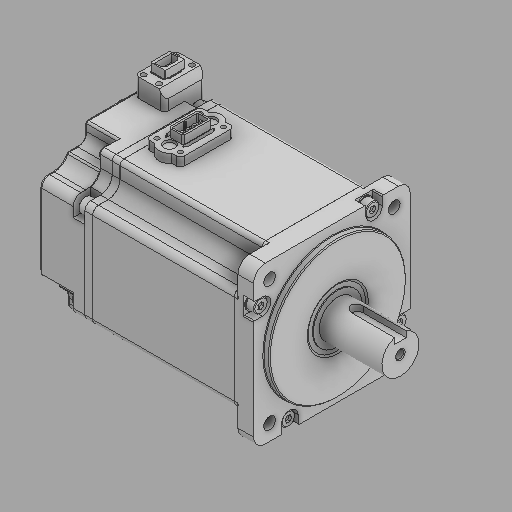
# Autodesk Inventor part: MSME082G1U_msmf_gh
Saved by Autodesk Inventor 2025.3 (Build 293356000, 356)
## iProperties
Category: PARTsolutions
Company: MATSUSHITA
Created: 2026-08-05
Part Number: MSME082G1U_msmf_gh
Material: Generisch
Catalog Web Link: www.3dfindit.com
Description: MSMF-gh-
Vendor: MATSUSHITA
Document SubType Name: Modeling
Designer: psAdmin
Manufacturer: MATSUSHITA
Mass: 644.906 g
Surface Area: 626.219 cm^2
Volume: 644.906 cm^3
Density: 1 g/cm^3
Appearance: PSOLRGB-176-176-176
PSOL_IDENT_0: {$CADENAS_DATA/23d-libs/matsushita/ac_servo_motor/servo_motor_wtout_gear/parts/a6_msmf_gear_head.prj
PSOL_IDENT_1: },185 {VTYP=3D},{NB=MSME082G1U_msmf_gh},{LINA=MSME082G1U},{NN=MSMF-gh},{DATE=04.12.2025 07:26:10},{G
PSOL_IDENT_2: EOMDATE=13.11.2025 11:41:00},{VERSION=},{LINEID=80},{WBVAR=E,B,EOS,OS,MS,PS},{WBNUMERIC=}  {NB=MSME0
PSOL_IDENT_3: 82G1U_msmf_gh},{LINA=MSME082G1U},{KT=DUMMY},{R=0.75 k},{E=G},{B=No},{EOS=With key and end of tap},{O
PSOL_IDENT_4: S=Yes},{MS=2},{PS=200},{CNSORDERNO=MSME082G1U},{X=U},{XR=08},{LM=114.5},{S=19},{X1=6},{KB1=56.5},{LR=
PSOL_IDENT_5: 55},{LK=42},{LH=45},{R1= '1.0 k','1.5 k','2.0 k','3.0 k','4.0 k','5.0 k' },{PS1=2},{PS2='200','400'}
PSOL_IDENT_6: ,{EOSX='Straight','Straight','D cut','D cut','With key and end of tap','With key and end of tap'},{O
PSOL_IDENT_7: SX='Yes','Yes','No','No'},{Z=5},{LX=147.2},{LLX=112.2},{LMX=86.2},{LTX=26},{LNX=0},{KB1X=52.4},{KB2X=
PSOL_IDENT_8: 85.7},{KB3X=0},{MS1= '2','IP67 motor' },{MS2=1},{XS=1},{BR=0},{XX=1}
NB: MSME082G1U_msmf_gh
NN: MSMF-gh
NBSYN: $CNSORDERNO._msmf_gh
LINA: MSME082G1U
CATALOG: Panasonic Industry Co., Ltd. , Motors for FA & Industrial Application
R: 0.75 k
E: 20bit Incremental
B: No
EOS: With key and end of tap
OS: Yes
MS: IP67 motor
PS: 200
CNSORDERNO: MSME082G1U
X1: 6
SUPPLIER: MATSUSHITA
ARTICLENO: MSME082G1U_msmf_gh
BOMINFO: MSME082G1U
CREATOR: CADENAS GmbH
Title: MSME082G1U
Author: Cadenas PARTsolutions
Autodesk Inventor part; units mm, degrees
ref_plane "YZ Plane" through (0, 0, 0) normal (1, 0, 0) x (0, 1, 0)
ref_plane "XZ Plane" through (0, 0, 0) normal (0, 1, 0) x (-1, 0, 0)
ref_plane "XY Plane" through (0, 0, 0) normal (0, 0, 1) x (1, 0, 0)
sketch "Sketch_3" plane through (0, 0, 0) normal (0, 0, 1) x (1, 0, 0)
  line L0 (0, 0) -> (-3, 0)
  line L1 (-3.5, 0) -> (-3.5, 35.5)
  line L2 (-3.5, 35.5) -> (-3, 35.5)
  line L3 (-3, 35.5) -> (-3, 35.3)
  arc A0 (-3, 35.3) -> (-2.7, 35) centre (-2.7, 35.3) ccw
  line L4 (-2.7, 35) -> (-0.5, 35)
  line L5 (-0.5, 35) -> (0, 34.5)
  line L6 (0, 34.5) -> (0, 15.566)
  line L7 (0, 15.566) -> (-0.5, 14.7)
  line L8 (-0.5, 14.7) -> (-0.5, 12.5)
  line L9 (-0.5, 12.5) -> (0, 12.5)
  line L10 (0, 12.5) -> (0, 0)
  line L11 (0, 0) -> (-3.5, 0)
  constraints: 24 end point, 2 point on circle, 1 centre point
revolve "Revolution1" add sketch "Sketch_3" angle 360 about axis through (0, 0, 0) along (1, 0, 0)
sketch "Sketch_2" plane through (0, 0, 0) normal (0, 0, 1) x (1, 0, 0)
  line L0 (32, 0) -> (0, 0)
  line L1 (0, 0) -> (0, 9.5)
  line L2 (0, 9.5) -> (32, 9.5)
  line L3 (32, 9.5) -> (32, 0)
  line L4 (32, 0) -> (0, 0)
  constraints: 10 end point
revolve "Revolution2" add sketch "Sketch_2" angle 360 about axis through (32, 0, 0) along (1, 0, 0)
sketch "Sketch_4" plane through (0, 6, 0) normal (0, 1, 0) x (1, 0, 0)
  arc A0 (10, 3) -> (10, -3) centre (10, 0) ccw
  line L0 (10, -3) -> (32, -3)
  line L1 (32, -3) -> (32, 3)
  line L2 (32, 3) -> (10, 3)
  constraints: 6 end point, 2 point on circle, 1 centre point
extrude "Extrusion1" cut sketch "Sketch_4" along normal blind 10
sketch "Sketch4" plane through (32, 6, 3) normal (1, 0, 0) x (0, 0, -1)
  point P0 (3, -6)
hole "Hole1" at (32, 0, 0) direction (-1, 0, 0) diameter 4.134 depth 11.8066 tip angle 120 countersink diameter 5 countersink angle 90 thread size "M5x0.8" class "6H" standard "ISO Metric profile"
sketch "Sketch_9" plane through (-3, 0, 0) normal (1, 0, 0) x (0, 0, -1)
  arc A0 (-40, -34) -> (-34, -40) centre (-34, -34) ccw
  line L0 (-34, -40) -> (34, -40)
  arc A1 (34, -40) -> (40, -34) centre (34, -34) ccw
  line L1 (40, -34) -> (40, 34)
  arc A2 (40, 34) -> (34, 40) centre (34, 34) ccw
  line L2 (34, 40) -> (-34, 40)
  arc A3 (-34, 40) -> (-40, 34) centre (-34, 34) ccw
  line L3 (-40, 34) -> (-40, -34)
  circle A4 centre (31.8198, 31.8198) radius 3
  circle A5 centre (31.8198, -31.8198) radius 3
  circle A6 centre (-31.8198, 31.8198) radius 3
  circle A7 centre (-31.8198, -31.8198) radius 3
  constraints: 8 centre point, 8 end point, 8 point on circle
extrude "Extrusion2" add sketch "Sketch_9" against normal blind 8
sketch "Sketch_10" plane through (-3, 0, 0) normal (1, 0, 0) x (0, 0, -1)
  line L0 (-40.5, 26.75) -> (-40.5, 16.25)
  line L1 (-40.5, 16.25) -> (-40, 16.25)
  line L2 (-40, 16.25) -> (-40, 16.75)
  arc A0 (-39.5, 17.25) -> (-40, 16.75) centre (-39.5, 16.75) ccw
  line L3 (-39.5, 17.25) -> (-35.5, 17.25)
  arc A1 (-35.5, 17.25) -> (-35.5, 25.75) centre (-35.5, 21.5) ccw
  line L4 (-35.5, 25.75) -> (-39.5, 25.75)
  arc A2 (-40, 26.25) -> (-39.5, 25.75) centre (-39.5, 26.25) ccw
  line L5 (-40, 26.25) -> (-40, 26.75)
  line L6 (-40, 26.75) -> (-40.5, 26.75)
  constraints: 14 end point, 6 point on circle, 3 centre point
extrude "Extrusion3" cut sketch "Sketch_10" against normal blind 5.1
sketch "Sketch_11" plane through (-3, 0, 0) normal (1, 0, 0) x (0, 0, -1)
  line L0 (16.25, 40) -> (16.75, 40)
  arc A0 (17.25, 39.5) -> (16.75, 40) centre (16.75, 39.5) ccw
  line L1 (17.25, 39.5) -> (17.25, 35.5)
  arc A1 (17.25, 35.5) -> (25.75, 35.5) centre (21.5, 35.5) ccw
  line L2 (25.75, 35.5) -> (25.75, 39.5)
  arc A2 (26.25, 40) -> (25.75, 39.5) centre (26.25, 39.5) ccw
  line L3 (26.25, 40) -> (26.75, 40)
  line L4 (26.75, 40) -> (26.75, 40.5)
  line L5 (26.75, 40.5) -> (16.25, 40.5)
  line L6 (16.25, 40.5) -> (16.25, 40)
  constraints: 14 end point, 6 point on circle, 3 centre point
extrude "Extrusion4" cut sketch "Sketch_11" against normal blind 5.1
sketch "Sketch_12" plane through (-3, 0, 0) normal (1, 0, 0) x (0, 0, -1)
  arc A0 (35.5, -17.25) -> (35.5, -25.75) centre (35.5, -21.5) ccw
  line L0 (35.5, -25.75) -> (39.5, -25.75)
  arc A1 (40, -26.25) -> (39.5, -25.75) centre (39.5, -26.25) ccw
  line L1 (40, -26.25) -> (40, -26.75)
  line L2 (40, -26.75) -> (40.5, -26.75)
  line L3 (40.5, -26.75) -> (40.5, -16.25)
  line L4 (40.5, -16.25) -> (40, -16.25)
  line L5 (40, -16.25) -> (40, -16.75)
  arc A2 (39.5, -17.25) -> (40, -16.75) centre (39.5, -16.75) ccw
  line L6 (39.5, -17.25) -> (35.5, -17.25)
  constraints: 14 end point, 6 point on circle, 3 centre point
extrude "Extrusion5" cut sketch "Sketch_12" against normal blind 5.1
sketch "Sketch_13" plane through (-3, 0, 0) normal (1, 0, 0) x (0, 0, -1)
  line L0 (-26.75, -40.5) -> (-16.25, -40.5)
  line L1 (-16.25, -40.5) -> (-16.25, -40)
  line L2 (-16.25, -40) -> (-16.75, -40)
  arc A0 (-17.25, -39.5) -> (-16.75, -40) centre (-16.75, -39.5) ccw
  line L3 (-17.25, -39.5) -> (-17.25, -35.5)
  arc A1 (-17.25, -35.5) -> (-25.75, -35.5) centre (-21.5, -35.5) ccw
  line L4 (-25.75, -35.5) -> (-25.75, -39.5)
  arc A2 (-26.25, -40) -> (-25.75, -39.5) centre (-26.25, -39.5) ccw
  line L5 (-26.25, -40) -> (-26.75, -40)
  line L6 (-26.75, -40) -> (-26.75, -40.5)
  constraints: 14 end point, 6 point on circle, 3 centre point
extrude "Extrusion6" cut sketch "Sketch_13" against normal blind 5.1
sketch "Sketch_14" plane through (0, 0, 35.5) normal (0, 0, 1) x (1, 0, 0)
  line L0 (-3.72, 21.5) -> (-8.1, 21.5)
  line L1 (-8.1, 21.5) -> (-8.1, 25.5)
  line L2 (-8.1, 25.5) -> (-7.7, 25.5)
  line L3 (-7.7, 25.5) -> (-7.7, 25)
  line L4 (-7.7, 25) -> (-4.07, 25)
  line L5 (-4.07, 25) -> (-3.72, 24.65)
  line L6 (-3.72, 24.65) -> (-3.72, 21.5)
  line L7 (-3.72, 21.5) -> (-8.1, 21.5)
  constraints: 16 end point
revolve "Revolution3" add sketch "Sketch_14" angle 360 about axis through (-3.72, 21.5, 35.5) along (1, 0, 0)
sketch "Sketch_15" plane through (0, 0, -35.5) normal (0, 0, 1) x (1, 0, 0)
  line L0 (-3.72, -21.5) -> (-8.1, -21.5)
  line L1 (-8.1, -21.5) -> (-8.1, -17.5)
  line L2 (-8.1, -17.5) -> (-7.7, -17.5)
  line L3 (-7.7, -17.5) -> (-7.7, -18)
  line L4 (-7.7, -18) -> (-4.07, -18)
  line L5 (-4.07, -18) -> (-3.72, -18.35)
  line L6 (-3.72, -18.35) -> (-3.72, -21.5)
  line L7 (-3.72, -21.5) -> (-8.1, -21.5)
  constraints: 16 end point
revolve "Revolution4" add sketch "Sketch_15" angle 360 about axis through (-3.72, -21.5, -35.5) along (1, 0, 0)
sketch "Sketch_16" plane through (0, -35.5, 0) normal (0, 1, 0) x (1, 0, 0)
  line L0 (-3.72, -21.5) -> (-8.1, -21.5)
  line L1 (-8.1, -21.5) -> (-8.1, -17.5)
  line L2 (-8.1, -17.5) -> (-7.7, -17.5)
  line L3 (-7.7, -17.5) -> (-7.7, -18)
  line L4 (-7.7, -18) -> (-4.07, -18)
  line L5 (-4.07, -18) -> (-3.72, -18.35)
  line L6 (-3.72, -18.35) -> (-3.72, -21.5)
  line L7 (-3.72, -21.5) -> (-8.1, -21.5)
  constraints: 16 end point
revolve "Revolution5" add sketch "Sketch_16" angle 360 about axis through (-3.72, -35.5, 21.5) along (1, 0, 0)
sketch "Sketch_17" plane through (0, 35.5, 0) normal (0, 1, 0) x (1, 0, 0)
  line L0 (-3.72, 21.5) -> (-8.1, 21.5)
  line L1 (-8.1, 21.5) -> (-8.1, 25.5)
  line L2 (-8.1, 25.5) -> (-7.7, 25.5)
  line L3 (-7.7, 25.5) -> (-7.7, 25)
  line L4 (-7.7, 25) -> (-4.07, 25)
  line L5 (-4.07, 25) -> (-3.72, 24.65)
  line L6 (-3.72, 24.65) -> (-3.72, 21.5)
  line L7 (-3.72, 21.5) -> (-8.1, 21.5)
  constraints: 16 end point
revolve "Revolution6" add sketch "Sketch_17" angle 360 about axis through (-3.72, 35.5, -21.5) along (1, 0, 0)
sketch "Sketch_18" plane through (-3.72, 0, 0) normal (1, 0, 0) x (0, 0, -1)
  line L0 (-37, 20.634) -> (-35.5, 19.7679)
  line L1 (-35.5, 19.7679) -> (-34, 20.634)
  line L2 (-34, 20.634) -> (-34, 22.366)
  line L3 (-34, 22.366) -> (-35.5, 23.2321)
  line L4 (-35.5, 23.2321) -> (-37, 22.366)
  line L5 (-37, 22.366) -> (-37, 20.634)
  constraints: 12 end point
extrude "Extrusion7" cut sketch "Sketch_18" against normal blind 1.255
sketch "Sketch_19" plane through (-3.72, 0, 0) normal (1, 0, 0) x (0, 0, -1)
  line L0 (19.7679, 35.5) -> (20.634, 34)
  line L1 (20.634, 34) -> (22.366, 34)
  line L2 (22.366, 34) -> (23.2321, 35.5)
  line L3 (23.2321, 35.5) -> (22.366, 37)
  line L4 (22.366, 37) -> (20.634, 37)
  line L5 (20.634, 37) -> (19.7679, 35.5)
  constraints: 12 end point
extrude "Extrusion8" cut sketch "Sketch_19" against normal blind 1.25
sketch "Sketch_20" plane through (-3.72, 0, 0) normal (1, 0, 0) x (0, 0, -1)
  line L0 (34, -22.366) -> (35.5, -23.2321)
  line L1 (35.5, -23.2321) -> (37, -22.366)
  line L2 (37, -22.366) -> (37, -20.634)
  line L3 (37, -20.634) -> (35.5, -19.7679)
  line L4 (35.5, -19.7679) -> (34, -20.634)
  line L5 (34, -20.634) -> (34, -22.366)
  constraints: 12 end point
extrude "Extrusion9" cut sketch "Sketch_20" against normal blind 1.25
sketch "Sketch_21" plane through (-3.72, 0, 0) normal (1, 0, 0) x (0, 0, -1)
  line L0 (-23.2321, -35.5) -> (-22.366, -37)
  line L1 (-22.366, -37) -> (-20.634, -37)
  line L2 (-20.634, -37) -> (-19.7679, -35.5)
  line L3 (-19.7679, -35.5) -> (-20.634, -34)
  line L4 (-20.634, -34) -> (-22.366, -34)
  line L5 (-22.366, -34) -> (-23.2321, -35.5)
  constraints: 12 end point
extrude "Extrusion10" cut sketch "Sketch_21" against normal blind 1.25
sketch "Sketch_22" plane through (-11, 0, 0) normal (1, 0, 0) x (0, 0, -1)
  arc A0 (-40, -23) -> (-37, -26) centre (-37, -23) ccw
  line L0 (-37, -26) -> (-32, -26)
  arc A1 (-26, -32) -> (-32, -26) centre (-32, -32) ccw
  line L1 (-26, -32) -> (-26, -37)
  arc A2 (-26, -37) -> (-23, -40) centre (-23, -37) ccw
  line L2 (-23, -40) -> (23, -40)
  arc A3 (23, -40) -> (26, -37) centre (23, -37) ccw
  line L3 (26, -37) -> (26, -32)
  arc A4 (32, -26) -> (26, -32) centre (32, -32) ccw
  line L4 (32, -26) -> (37, -26)
  arc A5 (37, -26) -> (40, -23) centre (37, -23) ccw
  line L5 (40, -23) -> (40, 23)
  arc A6 (40, 23) -> (37, 26) centre (37, 23) ccw
  line L6 (37, 26) -> (32, 26)
  arc A7 (26, 32) -> (32, 26) centre (32, 32) ccw
  line L7 (26, 32) -> (26, 38)
  arc A8 (26, 38) -> (24, 40) centre (24, 38) ccw
  line L8 (24, 40) -> (-24, 40)
  arc A9 (-24, 40) -> (-26, 38) centre (-24, 38) ccw
  line L9 (-26, 38) -> (-26, 32)
  arc A10 (-32, 26) -> (-26, 32) centre (-32, 32) ccw
  line L10 (-32, 26) -> (-37, 26)
  arc A11 (-37, 26) -> (-40, 23) centre (-37, 23) ccw
  line L11 (-40, 23) -> (-40, -23)
  constraints: 24 end point, 24 point on circle, 12 centre point
extrude "Extrusion11" add sketch "Sketch_22" against normal blind 74.2
sketch "Sketch_23" plane through (-12.8, 0, 0) normal (1, 0, 0) x (0, 0, -1)
  line L0 (-50, 50) -> (-50, -50)
  line L1 (-50, -50) -> (50, -50)
  line L2 (50, -50) -> (50, 50)
  line L3 (50, 50) -> (-50, 50)
  arc A0 (-36, -20.7) -> (-33.3, -23.4) centre (-33.3, -20.7) ccw
  line L4 (-33.3, -23.4) -> (-28.8, -23.4)
  arc A1 (-23.4, -28.8) -> (-28.8, -23.4) centre (-28.8, -28.8) ccw
  line L5 (-23.4, -28.8) -> (-23.4, -33.3)
  arc A2 (-23.4, -33.3) -> (-20.7, -36) centre (-20.7, -33.3) ccw
  line L6 (-20.7, -36) -> (20.7, -36)
  arc A3 (20.7, -36) -> (23.4, -33.3) centre (20.7, -33.3) ccw
  line L7 (23.4, -33.3) -> (23.4, -28.8)
  arc A4 (28.8, -23.4) -> (23.4, -28.8) centre (28.8, -28.8) ccw
  line L8 (28.8, -23.4) -> (33.3, -23.4)
  arc A5 (33.3, -23.4) -> (36, -20.7) centre (33.3, -20.7) ccw
  line L9 (36, -20.7) -> (36, 20.7)
  arc A6 (36, 20.7) -> (33.3, 23.4) centre (33.3, 20.7) ccw
  line L10 (33.3, 23.4) -> (28.8, 23.4)
  arc A7 (23.4, 28.8) -> (28.8, 23.4) centre (28.8, 28.8) ccw
  line L11 (23.4, 28.8) -> (23.4, 34.2)
  arc A8 (23.4, 34.2) -> (21.6, 36) centre (21.6, 34.2) ccw
  line L12 (21.6, 36) -> (-21.6, 36)
  arc A9 (-21.6, 36) -> (-23.4, 34.2) centre (-21.6, 34.2) ccw
  line L13 (-23.4, 34.2) -> (-23.4, 28.8)
  arc A10 (-28.8, 23.4) -> (-23.4, 28.8) centre (-28.8, 28.8) ccw
  line L14 (-28.8, 23.4) -> (-33.3, 23.4)
  arc A11 (-33.3, 23.4) -> (-36, 20.7) centre (-33.3, 20.7) ccw
  line L15 (-36, 20.7) -> (-36, -20.7)
  constraints: 32 end point, 24 point on circle, 12 centre point
extrude "Extrusion12" cut sketch "Sketch_23" against normal blind 0.05
sketch "Sketch_25" plane through (-85.2, 0, 0) normal (1, 0, 0) x (0, 0, -1)
  arc A0 (-40, -23) -> (-37, -26) centre (-37, -23) ccw
  line L0 (-37, -26) -> (-32, -26)
  arc A1 (-26, -32) -> (-32, -26) centre (-32, -32) ccw
  line L1 (-26, -32) -> (-26, -37)
  arc A2 (-26, -37) -> (-23, -40) centre (-23, -37) ccw
  line L2 (-23, -40) -> (23, -40)
  arc A3 (23, -40) -> (26, -37) centre (23, -37) ccw
  line L3 (26, -37) -> (26, -32)
  arc A4 (32, -26) -> (26, -32) centre (32, -32) ccw
  line L4 (32, -26) -> (37, -26)
  arc A5 (37, -26) -> (40, -23) centre (37, -23) ccw
  line L5 (40, -23) -> (40, 23)
  arc A6 (40, 23) -> (37, 26) centre (37, 23) ccw
  line L6 (37, 26) -> (32, 26)
  arc A7 (26, 32) -> (32, 26) centre (32, 32) ccw
  line L7 (26, 32) -> (26, 38)
  arc A8 (26, 38) -> (24, 40) centre (24, 38) ccw
  line L8 (24, 40) -> (-24, 40)
  arc A9 (-24, 40) -> (-26, 38) centre (-24, 38) ccw
  line L9 (-26, 38) -> (-26, 32)
  arc A10 (-32, 26) -> (-26, 32) centre (-32, 32) ccw
  line L10 (-32, 26) -> (-37, 26)
  arc A11 (-37, 26) -> (-40, 23) centre (-37, 23) ccw
  line L11 (-40, 23) -> (-40, -23)
  constraints: 24 end point, 24 point on circle, 12 centre point
extrude "Extrusion13" add sketch "Sketch_25" against normal blind 10
sketch "Sketch_26" plane through (-85.2, 0, 0) normal (1, 0, 0) x (0, 0, -1)
  line L0 (-50, 50) -> (-50, -50)
  line L1 (-50, -50) -> (50, -50)
  line L2 (50, -50) -> (50, 50)
  line L3 (50, 50) -> (-50, 50)
  arc A0 (-36, -20.7) -> (-33.3, -23.4) centre (-33.3, -20.7) ccw
  line L4 (-33.3, -23.4) -> (-28.8, -23.4)
  arc A1 (-23.4, -28.8) -> (-28.8, -23.4) centre (-28.8, -28.8) ccw
  line L5 (-23.4, -28.8) -> (-23.4, -33.3)
  arc A2 (-23.4, -33.3) -> (-20.7, -36) centre (-20.7, -33.3) ccw
  line L6 (-20.7, -36) -> (20.7, -36)
  arc A3 (20.7, -36) -> (23.4, -33.3) centre (20.7, -33.3) ccw
  line L7 (23.4, -33.3) -> (23.4, -28.8)
  arc A4 (28.8, -23.4) -> (23.4, -28.8) centre (28.8, -28.8) ccw
  line L8 (28.8, -23.4) -> (33.3, -23.4)
  arc A5 (33.3, -23.4) -> (36, -20.7) centre (33.3, -20.7) ccw
  line L9 (36, -20.7) -> (36, 20.7)
  arc A6 (36, 20.7) -> (33.3, 23.4) centre (33.3, 20.7) ccw
  line L10 (33.3, 23.4) -> (28.8, 23.4)
  arc A7 (23.4, 28.8) -> (28.8, 23.4) centre (28.8, 28.8) ccw
  line L11 (23.4, 28.8) -> (23.4, 34.2)
  arc A8 (23.4, 34.2) -> (21.6, 36) centre (21.6, 34.2) ccw
  line L12 (21.6, 36) -> (-21.6, 36)
  arc A9 (-21.6, 36) -> (-23.4, 34.2) centre (-21.6, 34.2) ccw
  line L13 (-23.4, 34.2) -> (-23.4, 28.8)
  arc A10 (-28.8, 23.4) -> (-23.4, 28.8) centre (-28.8, 28.8) ccw
  line L14 (-28.8, 23.4) -> (-33.3, 23.4)
  arc A11 (-33.3, 23.4) -> (-36, 20.7) centre (-33.3, 20.7) ccw
  line L15 (-36, 20.7) -> (-36, -20.7)
  constraints: 32 end point, 24 point on circle, 12 centre point
extrude "Extrusion14" cut sketch "Sketch_26" against normal blind 0.05
sketch "Sketch_27" plane through (-95.2, 0, 0) normal (1, 0, 0) x (0, 0, -1)
  arc A0 (-40, -16) -> (-39, -17) centre (-39, -16) ccw
  line L0 (-39, -17) -> (-35.5, -17)
  arc A1 (-31, -21.5) -> (-35.5, -17) centre (-35.5, -21.5) ccw
  line L1 (-31, -21.5) -> (-31, -25.754)
  arc A2 (-31, -25.754) -> (-30.4118, -26.6653) centre (-30, -25.754) ccw
  arc A3 (-26, -33.5) -> (-30.4118, -26.6653) centre (-33.5, -33.5) ccw
  line L2 (-26, -33.5) -> (-26, -36)
  arc A4 (-26, -36) -> (-22, -40) centre (-22, -36) ccw
  line L3 (-22, -40) -> (16, -40)
  arc A5 (16, -40) -> (17, -39) centre (16, -39) ccw
  line L4 (17, -39) -> (17, -35.5)
  arc A6 (21.5, -31) -> (17, -35.5) centre (21.5, -35.5) ccw
  line L5 (21.5, -31) -> (25.754, -31)
  arc A7 (25.754, -31) -> (26.6653, -30.4118) centre (25.754, -30) ccw
  arc A8 (33.5, -26) -> (26.6653, -30.4118) centre (33.5, -33.5) ccw
  line L6 (33.5, -26) -> (36, -26)
  arc A9 (36, -26) -> (40, -22) centre (36, -22) ccw
  line L7 (40, -22) -> (40, 22.25)
  arc A10 (40, 22.25) -> (36.25, 26) centre (36.25, 22.25) ccw
  line L8 (36.25, 26) -> (31.75, 26)
  arc A11 (27.5, 30.25) -> (31.75, 26) centre (31.75, 30.25) ccw
  line L9 (27.5, 30.25) -> (27.5, 40)
  line L10 (27.5, 40) -> (-16, 40)
  arc A12 (-16, 40) -> (-17, 39) centre (-16, 39) ccw
  line L11 (-17, 39) -> (-17, 35.5)
  arc A13 (-21.5, 31) -> (-17, 35.5) centre (-21.5, 35.5) ccw
  line L12 (-21.5, 31) -> (-25.754, 31)
  arc A14 (-25.754, 31) -> (-26.6653, 30.4118) centre (-25.754, 30) ccw
  arc A15 (-33.5, 26) -> (-26.6653, 30.4118) centre (-33.5, 33.5) ccw
  line L13 (-33.5, 26) -> (-36, 26)
  arc A16 (-36, 26) -> (-40, 22) centre (-36, 22) ccw
  line L14 (-40, 22) -> (-40, -16)
  constraints: 34 point on circle, 30 end point, 17 centre point
extrude "Extrusion15" add sketch "Sketch_27" against normal blind 16
sketch "Sketch_30" plane through (-95.2, 0, 0) normal (1, 0, 0) x (0, 0, -1)
  line L0 (-40, 27) -> (-40, 17)
  line L1 (-40, 17) -> (-31, 17)
  line L2 (-31, 17) -> (-31, 27)
  line L3 (-31, 27) -> (-40, 27)
  constraints: 8 end point
extrude "Extrusion16" cut sketch "Sketch_30" along normal blind 6
sketch "Sketch_32" plane through (-95.2, 0, 0) normal (1, 0, 0) x (0, 0, -1)
  line L0 (-27, -31) -> (-27, -40)
  line L1 (-27, -40) -> (-17, -40)
  line L2 (-17, -40) -> (-17, -31)
  line L3 (-17, -31) -> (-27, -31)
  constraints: 8 end point
extrude "Extrusion17" cut sketch "Sketch_32" along normal blind 6
sketch "Sketch_31" plane through (-95.2, 0, 0) normal (1, 0, 0) x (0, 0, -1)
  line L0 (31, -27) -> (40, -27)
  line L1 (40, -27) -> (40, -17)
  line L2 (40, -17) -> (31, -17)
  line L3 (31, -17) -> (31, -27)
  constraints: 8 end point
extrude "Extrusion18" cut sketch "Sketch_31" along normal blind 6
sketch "Sketch_33" plane through (-95.2, 0, 0) normal (1, 0, 0) x (0, 0, -1)
  line L0 (17, 31) -> (27, 31)
  line L1 (27, 31) -> (27, 40)
  line L2 (27, 40) -> (17, 40)
  line L3 (17, 40) -> (17, 31)
  constraints: 8 end point
extrude "Extrusion19" cut sketch "Sketch_33" along normal blind 6
sketch "Sketch_28" plane through (-89.2, 0, 0) normal (1, 0, 0) x (0, 0, -1)
  line L0 (-50, 50) -> (-50, -50)
  line L1 (-50, -50) -> (50, -50)
  line L2 (50, -50) -> (50, 50)
  line L3 (50, 50) -> (-50, 50)
  arc A0 (-28, -16.1) -> (-25.9, -18.2) centre (-25.9, -16.1) ccw
  line L4 (-25.9, -18.2) -> (-22.4, -18.2)
  arc A1 (-18.2, -22.4) -> (-22.4, -18.2) centre (-22.4, -22.4) ccw
  line L5 (-18.2, -22.4) -> (-18.2, -25.9)
  arc A2 (-18.2, -25.9) -> (-16.1, -28) centre (-16.1, -25.9) ccw
  line L6 (-16.1, -28) -> (16.1, -28)
  arc A3 (16.1, -28) -> (18.2, -25.9) centre (16.1, -25.9) ccw
  line L7 (18.2, -25.9) -> (18.2, -22.4)
  arc A4 (22.4, -18.2) -> (18.2, -22.4) centre (22.4, -22.4) ccw
  line L8 (22.4, -18.2) -> (25.9, -18.2)
  arc A5 (25.9, -18.2) -> (28, -16.1) centre (25.9, -16.1) ccw
  line L9 (28, -16.1) -> (28, 16.1)
  arc A6 (28, 16.1) -> (25.9, 18.2) centre (25.9, 16.1) ccw
  line L10 (25.9, 18.2) -> (22.4, 18.2)
  arc A7 (18.2, 22.4) -> (22.4, 18.2) centre (22.4, 22.4) ccw
  line L11 (18.2, 22.4) -> (18.2, 26.6)
  arc A8 (18.2, 26.6) -> (16.8, 28) centre (16.8, 26.6) ccw
  line L12 (16.8, 28) -> (-16.8, 28)
  arc A9 (-16.8, 28) -> (-18.2, 26.6) centre (-16.8, 26.6) ccw
  line L13 (-18.2, 26.6) -> (-18.2, 22.4)
  arc A10 (-22.4, 18.2) -> (-18.2, 22.4) centre (-22.4, 22.4) ccw
  line L14 (-22.4, 18.2) -> (-25.9, 18.2)
  arc A11 (-25.9, 18.2) -> (-28, 16.1) centre (-25.9, 16.1) ccw
  line L15 (-28, 16.1) -> (-28, -16.1)
  constraints: 32 end point, 24 point on circle, 12 centre point
extrude "Extrusion20" cut sketch "Sketch_28" against normal blind 0.05
sketch "Sketch_35" plane through (0, 40, 0) normal (0, 1, 0) x (1, 0, 0)
  line L0 (-84.2, 11.8) -> (-84.2, -11.8)
  arc A0 (-84.2, -11.8) -> (-82.2, -13.8) centre (-82.2, -11.8) ccw
  line L1 (-82.2, -13.8) -> (-79.8, -13.8)
  arc A1 (-79.8, -13.8) -> (-71, -13.8) centre (-75.4, -10.5) ccw
  line L2 (-71, -13.8) -> (-68.6, -13.8)
  arc A2 (-68.6, -13.8) -> (-66.6, -11.8) centre (-68.6, -11.8) ccw
  line L3 (-66.6, -11.8) -> (-66.6, 11.8)
  arc A3 (-66.6, 11.8) -> (-68.6, 13.8) centre (-68.6, 11.8) ccw
  line L4 (-68.6, 13.8) -> (-71, 13.8)
  arc A4 (-71, 13.8) -> (-79.8, 13.8) centre (-75.4, 10.5) ccw
  line L5 (-79.8, 13.8) -> (-82.2, 13.8)
  arc A5 (-82.2, 13.8) -> (-84.2, 11.8) centre (-82.2, 11.8) ccw
  circle A6 centre (-69.4, -11) radius 1.15
  circle A7 centre (-69.4, 11) radius 1.15
  circle A8 centre (-75.4, 10.5) radius 3
  circle A9 centre (-75.4, -10.5) radius 3
  circle A10 centre (-81.4, -11) radius 1.15
  circle A11 centre (-81.4, 11) radius 1.15
  constraints: 12 centre point, 12 end point, 12 point on circle
extrude "Extrusion21" add sketch "Sketch_35" along normal blind 4.5
sketch "Sketch_37" plane through (0, 44.5, 0) normal (0, 1, 0) x (1, 0, 0)
  line L0 (-71.4, 7.9517) -> (-71.4, -7.9517)
  arc A0 (-71.4, -7.9517) -> (-70.8402, -8.1017) centre (-71.1, -7.9517) ccw
  line L1 (-70.8402, -8.1017) -> (-69.934, -6.5321)
  arc A1 (-69.934, -6.5321) -> (-69.8, -6.0321) centre (-70.8, -6.0321) ccw
  line L2 (-69.8, -6.0321) -> (-69.8, 6.0321)
  arc A2 (-69.8, 6.0321) -> (-69.934, 6.5321) centre (-70.8, 6.0321) ccw
  line L3 (-69.934, 6.5321) -> (-70.8402, 8.1017)
  arc A3 (-70.8402, 8.1017) -> (-71.4, 7.9517) centre (-71.1, 7.9517) ccw
  constraints: 8 end point, 8 point on circle, 4 centre point
extrude "Extrusion22" cut sketch "Sketch_37" against normal blind 3
sketch "Sketch_36" plane through (0, 44.5, 0) normal (0, 1, 0) x (1, 0, 0)
  line L0 (-81, 6.0321) -> (-81, -6.0321)
  arc A0 (-81, -6.0321) -> (-80.866, -6.5321) centre (-80, -6.0321) ccw
  line L1 (-80.866, -6.5321) -> (-79.9598, -8.1017)
  arc A1 (-79.9598, -8.1017) -> (-79.4, -7.9517) centre (-79.7, -7.9517) ccw
  line L2 (-79.4, -7.9517) -> (-79.4, 7.9517)
  arc A2 (-79.4, 7.9517) -> (-79.9598, 8.1017) centre (-79.7, 7.9517) ccw
  line L3 (-79.9598, 8.1017) -> (-80.866, 6.5321)
  arc A3 (-80.866, 6.5321) -> (-81, 6.0321) centre (-80, 6.0321) ccw
  constraints: 8 end point, 8 point on circle, 4 centre point
extrude "Extrusion23" cut sketch "Sketch_36" against normal blind 3
sketch "Sketch_38" plane through (-75.4, 0, 0) normal (1, 0, 0) x (0, 0, -1)
  line L0 (-10.5, 40) -> (-10.5, 44.25)
  arc A0 (-7.75, 43.5) -> (-10.5, 44.25) centre (-11.0624, 36.7711) ccw
  line L1 (-7.75, 43.5) -> (-7.75, 40)
  line L2 (-7.75, 40) -> (-10.5, 40)
  line L3 (-10.5, 40) -> (-10.5, 44.25)
  constraints: 8 end point, 2 point on circle, 1 centre point
revolve "Revolution7" add sketch "Sketch_38" angle 360 about axis through (-75.4, 40, 10.5) along (0, -1, 0)
sketch "Sketch_39" plane through (-75.4, 0, 0) normal (1, 0, 0) x (0, 0, -1)
  line L0 (10.5, 40) -> (10.5, 44.25)
  arc A0 (13.25, 43.5) -> (10.5, 44.25) centre (9.9376, 36.7711) ccw
  line L1 (13.25, 43.5) -> (13.25, 40)
  line L2 (13.25, 40) -> (10.5, 40)
  line L3 (10.5, 40) -> (10.5, 44.25)
  constraints: 8 end point, 2 point on circle, 1 centre point
revolve "Revolution8" add sketch "Sketch_39" angle 360 about axis through (-75.4, 40, -10.5) along (0, -1, 0)
sketch "Sketch_40" plane through (0, 44.5, 0) normal (0, 1, 0) x (1, 0, 0)
  line L0 (-79.125, 6.5) -> (-79.125, -6.5)
  line L1 (-79.125, -6.5) -> (-78.325, -7.3)
  line L2 (-78.325, -7.3) -> (-72.475, -7.3)
  line L3 (-72.475, -7.3) -> (-71.675, -6.5)
  line L4 (-71.675, -6.5) -> (-71.675, 6.5)
  line L5 (-71.675, 6.5) -> (-72.475, 7.3)
  line L6 (-72.475, 7.3) -> (-78.325, 7.3)
  line L7 (-78.325, 7.3) -> (-79.125, 6.5)
  line L8 (-78.125, 6.15) -> (-78.125, -6.15)
  line L9 (-78.125, -6.15) -> (-77.825, -6.45)
  line L10 (-77.825, -6.45) -> (-72.975, -6.45)
  line L11 (-72.975, -6.45) -> (-72.675, -6.15)
  line L12 (-72.675, -6.15) -> (-72.675, 6.15)
  line L13 (-72.675, 6.15) -> (-72.975, 6.45)
  line L14 (-72.975, 6.45) -> (-77.825, 6.45)
  line L15 (-77.825, 6.45) -> (-78.125, 6.15)
  constraints: 32 end point
extrude "Extrusion24" add sketch "Sketch_40" along normal blind 4.1
sketch "Sketch_52" plane through (-111.9, 0, 0) normal (1, 0, 0) x (0, 0, -1)
  arc A0 (-39.75, -14.5) -> (-37.5, -16.75) centre (-37.5, -14.5) ccw
  line L0 (-37.5, -16.75) -> (-34, -16.75)
  arc A1 (-30.75, -20) -> (-34, -16.75) centre (-34, -20) ccw
  line L1 (-30.75, -20) -> (-30.75, -24.8397)
  arc A2 (-30.75, -24.8397) -> (-29.625, -26.7883) centre (-28.5, -24.8397) ccw
  arc A3 (-25.75, -33.5) -> (-29.625, -26.7883) centre (-33.5, -33.5) ccw
  line L2 (-25.75, -33.5) -> (-25.75, -36)
  arc A4 (-25.75, -36) -> (-22, -39.75) centre (-22, -36) ccw
  line L3 (-22, -39.75) -> (14.5, -39.75)
  arc A5 (14.5, -39.75) -> (16.75, -37.5) centre (14.5, -37.5) ccw
  line L4 (16.75, -37.5) -> (16.75, -34)
  arc A6 (20, -30.75) -> (16.75, -34) centre (20, -34) ccw
  line L5 (20, -30.75) -> (24.8397, -30.75)
  arc A7 (24.8397, -30.75) -> (26.7883, -29.625) centre (24.8397, -28.5) ccw
  arc A8 (33.5, -25.75) -> (26.7883, -29.625) centre (33.5, -33.5) ccw
  line L6 (33.5, -25.75) -> (36, -25.75)
  arc A9 (36, -25.75) -> (39.75, -22) centre (36, -22) ccw
  line L7 (39.75, -22) -> (39.75, 22)
  arc A10 (39.75, 22) -> (36, 25.75) centre (36, 22) ccw
  line L8 (36, 25.75) -> (31.5, 25.75)
  arc A11 (27.25, 30) -> (31.5, 25.75) centre (31.5, 30) ccw
  line L9 (27.25, 30) -> (27.25, 36.75)
  arc A12 (27.25, 36.75) -> (24.25, 39.75) centre (24.25, 36.75) ccw
  line L10 (24.25, 39.75) -> (-15.75, 39.75)
  arc A13 (-15.75, 39.75) -> (-16.75, 38.75) centre (-15.75, 38.75) ccw
  line L11 (-16.75, 38.75) -> (-16.75, 34)
  arc A14 (-20, 30.75) -> (-16.75, 34) centre (-20, 34) ccw
  line L12 (-20, 30.75) -> (-24.8397, 30.75)
  arc A15 (-24.8397, 30.75) -> (-26.7883, 29.625) centre (-24.8397, 28.5) ccw
  arc A16 (-33.5, 25.75) -> (-26.7883, 29.625) centre (-33.5, 33.5) ccw
  line L13 (-33.5, 25.75) -> (-36, 25.75)
  arc A17 (-36, 25.75) -> (-39.75, 22) centre (-36, 22) ccw
  line L14 (-39.75, 22) -> (-39.75, -14.5)
  constraints: 36 point on circle, 30 end point, 18 centre point
extrude "Extrusion25" add sketch "Sketch_52" along normal blind 1.2
sketch "Sketch_51" plane through (0, 0, 0) normal (0, 0, 1) x (1, 0, 0)
  line L0 (-111.9, 0) -> (-115.2, 0)
  line L1 (-115.2, 0) -> (-115.2, 23)
  line L2 (-115.2, 23) -> (-111.9, 27.6)
  line L3 (-111.9, 27.6) -> (-111.9, 0)
  line L4 (-111.9, 0) -> (-115.2, 0)
  constraints: 10 end point
revolve "Revolution9" add sketch "Sketch_51" angle 360 about axis through (-111.9, 0, 0) along (1, 0, 0)
sketch "Sketch_53" plane through (0, 40, 0) normal (0, 1, 0) x (1, 0, 0)
  arc A0 (-110.2, 8.5) -> (-108.2, 6.5) centre (-108.2, 8.5) ccw
  line L0 (-108.2, 6.5) -> (-97.2, 6.5)
  arc A1 (-97.2, 6.5) -> (-95.2, 8.5) centre (-97.2, 8.5) ccw
  line L1 (-95.2, 8.5) -> (-95.2, 25.5)
  arc A2 (-95.2, 25.5) -> (-97.2, 27.5) centre (-97.2, 25.5) ccw
  line L2 (-97.2, 27.5) -> (-108.2, 27.5)
  arc A3 (-108.2, 27.5) -> (-110.2, 25.5) centre (-108.2, 25.5) ccw
  line L3 (-110.2, 25.5) -> (-110.2, 8.5)
  constraints: 8 end point, 8 point on circle, 4 centre point
extrude "Extrusion26" add sketch "Sketch_53" along normal blind 5.5
sketch "Sketch_55" plane through (0, 45.5, 0) normal (0, 1, 0) x (1, 0, 0)
  arc A0 (-110.2, 8.5) -> (-108.2, 6.5) centre (-108.2, 8.5) ccw
  line L0 (-108.2, 6.5) -> (-97.2, 6.5)
  arc A1 (-97.2, 6.5) -> (-95.2, 8.5) centre (-97.2, 8.5) ccw
  line L1 (-95.2, 8.5) -> (-95.2, 25.5)
  arc A2 (-95.2, 25.5) -> (-97.2, 27.5) centre (-97.2, 25.5) ccw
  line L2 (-97.2, 27.5) -> (-108.2, 27.5)
  arc A3 (-108.2, 27.5) -> (-110.2, 25.5) centre (-108.2, 25.5) ccw
  line L3 (-110.2, 25.5) -> (-110.2, 8.5)
  constraints: 8 end point, 8 point on circle, 4 centre point
extrude "Extrusion27" add sketch "Sketch_55" along normal blind 4
sketch "Sketch_54" plane through (0, 49.5, 0) normal (0, 1, 0) x (1, 0, 0)
  arc A0 (-108.25, 14.25) -> (-107.75, 13.75) centre (-107.75, 14.25) ccw
  line L0 (-107.75, 13.75) -> (-107.45, 13.75)
  line L1 (-107.45, 13.75) -> (-107.45, 12)
  arc A1 (-107.45, 12) -> (-106.95, 11.5) centre (-106.95, 12) ccw
  line L2 (-106.95, 11.5) -> (-100.95, 11.5)
  arc A2 (-100.95, 11.5) -> (-100.45, 12) centre (-100.95, 12) ccw
  line L3 (-100.45, 12) -> (-100.45, 13.75)
  line L4 (-100.45, 13.75) -> (-100.15, 13.75)
  arc A3 (-100.15, 13.75) -> (-99.65, 14.25) centre (-100.15, 14.25) ccw
  line L5 (-99.65, 14.25) -> (-99.65, 19.85)
  arc A4 (-99.65, 19.85) -> (-100.15, 20.35) centre (-100.15, 19.85) ccw
  line L6 (-100.15, 20.35) -> (-100.45, 20.35)
  line L7 (-100.45, 20.35) -> (-100.45, 22.1)
  arc A5 (-100.45, 22.1) -> (-100.95, 22.6) centre (-100.95, 22.1) ccw
  line L8 (-100.95, 22.6) -> (-106.95, 22.6)
  arc A6 (-106.95, 22.6) -> (-107.45, 22.1) centre (-106.95, 22.1) ccw
  line L9 (-107.45, 22.1) -> (-107.45, 20.35)
  line L10 (-107.45, 20.35) -> (-107.75, 20.35)
  arc A7 (-107.75, 20.35) -> (-108.25, 19.85) centre (-107.75, 19.85) ccw
  line L11 (-108.25, 19.85) -> (-108.25, 14.25)
  arc A8 (-108, 14.25) -> (-107.75, 14) centre (-107.75, 14.25) ccw
  line L12 (-107.75, 14) -> (-107.2, 14)
  line L13 (-107.2, 14) -> (-107.2, 12)
  arc A9 (-107.2, 12) -> (-106.95, 11.75) centre (-106.95, 12) ccw
  line L14 (-106.95, 11.75) -> (-100.95, 11.75)
  arc A10 (-100.95, 11.75) -> (-100.7, 12) centre (-100.95, 12) ccw
  line L15 (-100.7, 12) -> (-100.7, 14)
  line L16 (-100.7, 14) -> (-100.15, 14)
  arc A11 (-100.15, 14) -> (-99.9, 14.25) centre (-100.15, 14.25) ccw
  line L17 (-99.9, 14.25) -> (-99.9, 19.85)
  arc A12 (-99.9, 19.85) -> (-100.15, 20.1) centre (-100.15, 19.85) ccw
  line L18 (-100.15, 20.1) -> (-100.7, 20.1)
  line L19 (-100.7, 20.1) -> (-100.7, 22.1)
  arc A13 (-100.7, 22.1) -> (-100.95, 22.35) centre (-100.95, 22.1) ccw
  line L20 (-100.95, 22.35) -> (-106.95, 22.35)
  arc A14 (-106.95, 22.35) -> (-107.2, 22.1) centre (-106.95, 22.1) ccw
  line L21 (-107.2, 22.1) -> (-107.2, 20.1)
  line L22 (-107.2, 20.1) -> (-107.75, 20.1)
  arc A15 (-107.75, 20.1) -> (-108, 19.85) centre (-107.75, 19.85) ccw
  line L23 (-108, 19.85) -> (-108, 14.25)
  constraints: 48 end point, 32 point on circle, 16 centre point
extrude "Extrusion28" cut sketch "Sketch_54" against normal blind 0.5
sketch "Sketch_56" plane through (0, 49.5, 0) normal (0, 1, 0) x (1, 0, 0)
  line L0 (-107.65, 12.3) -> (-107.45, 12.1)
  line L1 (-107.45, 12.1) -> (-100.45, 12.1)
  line L2 (-100.45, 12.1) -> (-100.25, 12.3)
  line L3 (-100.25, 12.3) -> (-100.25, 21.7)
  line L4 (-100.25, 21.7) -> (-100.45, 21.9)
  line L5 (-100.45, 21.9) -> (-107.45, 21.9)
  line L6 (-107.45, 21.9) -> (-107.65, 21.7)
  line L7 (-107.65, 21.7) -> (-107.65, 12.3)
  line L8 (-106.25, 12.75) -> (-103.15, 12.75)
  line L9 (-103.15, 12.75) -> (-101.65, 14.25)
  line L10 (-101.65, 14.25) -> (-101.65, 19.75)
  line L11 (-101.65, 19.75) -> (-103.15, 21.25)
  line L12 (-103.15, 21.25) -> (-106.25, 21.25)
  line L13 (-106.25, 21.25) -> (-106.25, 12.75)
  constraints: 28 end point
extrude "Extrusion29" add sketch "Sketch_56" along normal blind 4
sketch "Sketch40" plane through (0, 49.5, 0) normal (0, 1, 0) x (1, 0, 0)
  point P0 (-107.9, 8.7)
hole "Hole2" at (-107.9, 49.5, -8.7) direction (0, -1, 0) diameter 2.7 depth 2
sketch "Sketch41" plane through (0, 49.5, 0) normal (0, 1, 0) x (1, 0, 0)
  point P0 (-99.9, 8.7)
hole "Hole3" at (-99.9, 49.5, -8.7) direction (0, -1, 0) diameter 2.7 depth 2
sketch "Sketch42" plane through (0, 49.5, 0) normal (0, 1, 0) x (1, 0, 0)
  point P0 (-107.9, 25.3)
hole "Hole4" at (-107.9, 49.5, -25.3) direction (0, -1, 0) diameter 2.7 depth 2
sketch "Sketch43" plane through (0, 49.5, 0) normal (0, 1, 0) x (1, 0, 0)
  point P0 (-99.9, 25.3)
hole "Hole5" at (-99.9, 49.5, -25.3) direction (0, -1, 0) diameter 2.7 depth 2
sketch "Sketch_61" plane through (0, 0, -1.5) normal (0, 0, 1) x (1, 0, 0)
  line L0 (-111.9, 36.75) -> (-113.9, 36.75)
  arc A0 (-113.65, 38.7) -> (-113.9, 36.75) centre (-106.9006, 36.8437) ccw
  arc A1 (-112.75, 39.4) -> (-113.65, 38.7) centre (-112.6956, 38.4015) ccw
  line L1 (-112.75, 39.4) -> (-111.9, 39.5)
  line L2 (-111.9, 39.5) -> (-111.9, 36.75)
  line L3 (-111.9, 36.75) -> (-113.9, 36.75)
  constraints: 8 end point, 4 point on circle, 2 centre point
revolve "Revolution10" add sketch "Sketch_61" angle 360 about axis through (-111.9, 36.75, -1.5) along (1, 0, 0)
sketch "Sketch_62" plane through (0, 0, 35.5) normal (0, 0, 1) x (1, 0, 0)
  line L0 (-111.9, 21.5) -> (-113.9, 21.5)
  arc A0 (-113.65, 23.45) -> (-113.9, 21.5) centre (-106.9006, 21.5937) ccw
  arc A1 (-112.75, 24.15) -> (-113.65, 23.45) centre (-112.6956, 23.1515) ccw
  line L1 (-112.75, 24.15) -> (-111.9, 24.25)
  line L2 (-111.9, 24.25) -> (-111.9, 21.5)
  line L3 (-111.9, 21.5) -> (-113.9, 21.5)
  constraints: 8 end point, 4 point on circle, 2 centre point
revolve "Revolution11" add sketch "Sketch_62" angle 360 about axis through (-111.9, 21.5, 35.5) along (1, 0, 0)
sketch "Sketch_63" plane through (0, 0, 21.5) normal (0, 0, 1) x (1, 0, 0)
  line L0 (-111.9, -35.5) -> (-113.9, -35.5)
  arc A0 (-113.65, -33.55) -> (-113.9, -35.5) centre (-106.9006, -35.4063) ccw
  arc A1 (-112.75, -32.85) -> (-113.65, -33.55) centre (-112.6956, -33.8485) ccw
  line L1 (-112.75, -32.85) -> (-111.9, -32.75)
  line L2 (-111.9, -32.75) -> (-111.9, -35.5)
  line L3 (-111.9, -35.5) -> (-113.9, -35.5)
  constraints: 8 end point, 4 point on circle, 2 centre point
revolve "Revolution12" add sketch "Sketch_63" angle 360 about axis through (-111.9, -35.5, 21.5) along (1, 0, 0)
sketch "Sketch_64" plane through (0, 0, -35.5) normal (0, 0, 1) x (1, 0, 0)
  line L0 (-111.9, -21.5) -> (-113.9, -21.5)
  arc A0 (-113.65, -19.55) -> (-113.9, -21.5) centre (-106.9006, -21.4063) ccw
  arc A1 (-112.75, -18.85) -> (-113.65, -19.55) centre (-112.6956, -19.8485) ccw
  line L1 (-112.75, -18.85) -> (-111.9, -18.75)
  line L2 (-111.9, -18.75) -> (-111.9, -21.5)
  line L3 (-111.9, -21.5) -> (-113.9, -21.5)
  constraints: 8 end point, 4 point on circle, 2 centre point
revolve "Revolution13" add sketch "Sketch_64" angle 360 about axis through (-111.9, -21.5, -35.5) along (1, 0, 0)
sketch "Sketch_65" plane through (0, 0, -35.5) normal (0, 0, 1) x (1, 0, 0)
  line L0 (-112.2, 21.5) -> (-115.55, 21.5)
  arc A0 (-115.35, 23.1) -> (-115.55, 21.5) centre (-109.5503, 21.5625) ccw
  arc A1 (-114.65, 23.65) -> (-115.35, 23.1) centre (-114.5893, 22.8523) ccw
  line L1 (-114.65, 23.65) -> (-113.3, 23.75)
  line L2 (-113.3, 23.75) -> (-113.3, 23.9)
  line L3 (-113.3, 23.9) -> (-112.7, 23.9)
  line L4 (-112.7, 23.9) -> (-112.7, 24)
  line L5 (-112.7, 24) -> (-112.2, 24)
  line L6 (-112.2, 24) -> (-112.2, 24.175)
  line L7 (-112.2, 24.175) -> (-111.9, 24.175)
  line L8 (-111.9, 24.175) -> (-111.9, 21.5)
  line L9 (-111.9, 21.5) -> (-115.55, 21.5)
  constraints: 20 end point, 4 point on circle, 2 centre point
revolve "Revolution14" add sketch "Sketch_65" angle 360 about axis through (-112.2, 21.5, -35.5) along (1, 0, 0)
sketch "Sketch_66" plane through (0, 0, 21.5) normal (0, 0, 1) x (1, 0, 0)
  line L0 (-95.2, 35.5) -> (-98.4, 35.5)
  arc A0 (-98.2, 37.35) -> (-98.4, 35.5) centre (-91.4023, 35.6793) ccw
  arc A1 (-97.5, 38.15) -> (-98.2, 37.35) centre (-97.2125, 37.1922) ccw
  line L1 (-97.5, 38.15) -> (-96.4, 38.25)
  line L2 (-96.4, 38.25) -> (-95.7, 38.25)
  line L3 (-95.7, 38.25) -> (-95.7, 38.5)
  line L4 (-95.7, 38.5) -> (-95.2, 38.5)
  line L5 (-95.2, 38.5) -> (-95.2, 35.5)
  line L6 (-95.2, 35.5) -> (-98.4, 35.5)
  constraints: 14 end point, 4 point on circle, 2 centre point
revolve "Revolution15" add sketch "Sketch_66" angle 360 about axis through (-95.2, 35.5, 21.5) along (1, 0, 0)
sketch "Sketch_67" plane through (0, 0, -21.5) normal (0, 0, 1) x (1, 0, 0)
  line L0 (-95.2, -35.5) -> (-98.4, -35.5)
  arc A0 (-98.2, -33.65) -> (-98.4, -35.5) centre (-91.4023, -35.3207) ccw
  arc A1 (-97.5, -32.85) -> (-98.2, -33.65) centre (-97.2125, -33.8078) ccw
  line L1 (-97.5, -32.85) -> (-96.4, -32.75)
  line L2 (-96.4, -32.75) -> (-95.7, -32.75)
  line L3 (-95.7, -32.75) -> (-95.7, -32.5)
  line L4 (-95.7, -32.5) -> (-95.2, -32.5)
  line L5 (-95.2, -32.5) -> (-95.2, -35.5)
  line L6 (-95.2, -35.5) -> (-98.4, -35.5)
  constraints: 14 end point, 4 point on circle, 2 centre point
revolve "Revolution16" add sketch "Sketch_67" angle 360 about axis through (-95.2, -35.5, -21.5) along (1, 0, 0)
sketch "Sketch_68" plane through (0, 0, 35.5) normal (0, 0, 1) x (1, 0, 0)
  line L0 (-95.2, -21.5) -> (-98.4, -21.5)
  arc A0 (-98.2, -19.65) -> (-98.4, -21.5) centre (-91.4023, -21.3207) ccw
  arc A1 (-97.5, -18.85) -> (-98.2, -19.65) centre (-97.2125, -19.8078) ccw
  line L1 (-97.5, -18.85) -> (-96.4, -18.75)
  line L2 (-96.4, -18.75) -> (-95.7, -18.75)
  line L3 (-95.7, -18.75) -> (-95.7, -18.5)
  line L4 (-95.7, -18.5) -> (-95.2, -18.5)
  line L5 (-95.2, -18.5) -> (-95.2, -21.5)
  line L6 (-95.2, -21.5) -> (-98.4, -21.5)
  constraints: 14 end point, 4 point on circle, 2 centre point
revolve "Revolution17" add sketch "Sketch_68" angle 360 about axis through (-95.2, -21.5, 35.5) along (1, 0, 0)
sketch "Sketch_69" plane through (0, 0, 35.5) normal (0, 0, 1) x (1, 0, 0)
  line L0 (-89.2, 21.5) -> (-93.58, 21.5)
  line L1 (-93.58, 21.5) -> (-93.58, 24.65)
  line L2 (-93.58, 24.65) -> (-93.23, 25)
  line L3 (-93.23, 25) -> (-89.58, 25)
  line L4 (-89.58, 25) -> (-89.58, 25.5)
  line L5 (-89.58, 25.5) -> (-89.2, 25.5)
  line L6 (-89.2, 25.5) -> (-89.2, 21.5)
  line L7 (-89.2, 21.5) -> (-93.58, 21.5)
  constraints: 16 end point
revolve "Revolution18" add sketch "Sketch_69" angle 360 about axis through (-89.2, 21.5, 35.5) along (1, 0, 0)
sketch "Sketch_70" plane through (0, 0, 21.5) normal (0, 0, 1) x (1, 0, 0)
  line L0 (-89.2, -35.5) -> (-93.58, -35.5)
  line L1 (-93.58, -35.5) -> (-93.58, -32.35)
  line L2 (-93.58, -32.35) -> (-93.23, -32)
  line L3 (-93.23, -32) -> (-89.58, -32)
  line L4 (-89.58, -32) -> (-89.58, -31.5)
  line L5 (-89.58, -31.5) -> (-89.2, -31.5)
  line L6 (-89.2, -31.5) -> (-89.2, -35.5)
  line L7 (-89.2, -35.5) -> (-93.58, -35.5)
  constraints: 16 end point
revolve "Revolution19" add sketch "Sketch_70" angle 360 about axis through (-89.2, -35.5, 21.5) along (1, 0, 0)
sketch "Sketch_71" plane through (0, 0, -35.5) normal (0, 0, 1) x (1, 0, 0)
  line L0 (-89.2, -21.5) -> (-93.58, -21.5)
  line L1 (-93.58, -21.5) -> (-93.58, -18.35)
  line L2 (-93.58, -18.35) -> (-93.23, -18)
  line L3 (-93.23, -18) -> (-89.58, -18)
  line L4 (-89.58, -18) -> (-89.58, -17.5)
  line L5 (-89.58, -17.5) -> (-89.2, -17.5)
  line L6 (-89.2, -17.5) -> (-89.2, -21.5)
  line L7 (-89.2, -21.5) -> (-93.58, -21.5)
  constraints: 16 end point
revolve "Revolution20" add sketch "Sketch_71" angle 360 about axis through (-89.2, -21.5, -35.5) along (1, 0, 0)
sketch "Sketch_72" plane through (0, 0, -21.5) normal (0, 0, 1) x (1, 0, 0)
  line L0 (-89.2, 35.5) -> (-93.58, 35.5)
  line L1 (-93.58, 35.5) -> (-93.58, 38.65)
  line L2 (-93.58, 38.65) -> (-93.23, 39)
  line L3 (-93.23, 39) -> (-89.58, 39)
  line L4 (-89.58, 39) -> (-89.58, 39.5)
  line L5 (-89.58, 39.5) -> (-89.2, 39.5)
  line L6 (-89.2, 39.5) -> (-89.2, 35.5)
  line L7 (-89.2, 35.5) -> (-93.58, 35.5)
  constraints: 16 end point
revolve "Revolution21" add sketch "Sketch_72" angle 360 about axis through (-89.2, 35.5, -21.5) along (1, 0, 0)
sketch "Sketch_73" plane through (0, 44.5, 0) normal (0, 1, 0) x (1, 0, 0)
  line L0 (-75.49, 5.415) -> (-75.49, 4.185)
  line L1 (-75.49, 4.185) -> (-74.26, 4.185)
  line L2 (-74.26, 4.185) -> (-74.26, 5.415)
  line L3 (-74.26, 5.415) -> (-75.49, 5.415)
  constraints: 8 end point
extrude "Extrusion30" add sketch "Sketch_73" along normal blind 3
sketch "Sketch_74" plane through (0, 44.5, 0) normal (0, 1, 0) x (1, 0, 0)
  line L0 (-75.49, 2.215) -> (-75.49, 0.985)
  line L1 (-75.49, 0.985) -> (-74.26, 0.985)
  line L2 (-74.26, 0.985) -> (-74.26, 2.215)
  line L3 (-74.26, 2.215) -> (-75.49, 2.215)
  constraints: 8 end point
extrude "Extrusion31" add sketch "Sketch_74" along normal blind 3
sketch "Sketch_75" plane through (0, 44.5, 0) normal (0, 1, 0) x (1, 0, 0)
  line L0 (-75.49, -0.985) -> (-75.49, -2.215)
  line L1 (-75.49, -2.215) -> (-74.26, -2.215)
  line L2 (-74.26, -2.215) -> (-74.26, -0.985)
  line L3 (-74.26, -0.985) -> (-75.49, -0.985)
  constraints: 8 end point
extrude "Extrusion32" add sketch "Sketch_75" along normal blind 3
sketch "Sketch_76" plane through (0, 44.5, 0) normal (0, 1, 0) x (1, 0, 0)
  line L0 (-75.49, -4.185) -> (-75.49, -5.415)
  line L1 (-75.49, -5.415) -> (-74.26, -5.415)
  line L2 (-74.26, -5.415) -> (-74.26, -4.185)
  line L3 (-74.26, -4.185) -> (-75.49, -4.185)
  constraints: 8 end point
extrude "Extrusion33" add sketch "Sketch_76" along normal blind 3
sketch "Sketch_77" plane through (0, 44.5, 0) normal (0, 1, 0) x (1, 0, 0)
  arc A0 (-75.875, 3.1) -> (-75.725, 2.95) centre (-75.725, 3.1) ccw
  line L0 (-75.725, 2.95) -> (-74.025, 2.95)
  arc A1 (-74.025, 2.95) -> (-73.875, 3.1) centre (-74.025, 3.1) ccw
  line L1 (-73.875, 3.1) -> (-73.875, 3.3)
  arc A2 (-73.875, 3.3) -> (-74.025, 3.45) centre (-74.025, 3.3) ccw
  line L2 (-74.025, 3.45) -> (-75.725, 3.45)
  arc A3 (-75.725, 3.45) -> (-75.875, 3.3) centre (-75.725, 3.3) ccw
  line L3 (-75.875, 3.3) -> (-75.875, 3.1)
  constraints: 8 end point, 8 point on circle, 4 centre point
extrude "Extrusion34" add sketch "Sketch_77" along normal blind 1.5
sketch "Sketch_78" plane through (0, 44.5, 0) normal (0, 1, 0) x (1, 0, 0)
  arc A0 (-75.875, -0.1) -> (-75.725, -0.25) centre (-75.725, -0.1) ccw
  line L0 (-75.725, -0.25) -> (-74.025, -0.25)
  arc A1 (-74.025, -0.25) -> (-73.875, -0.1) centre (-74.025, -0.1) ccw
  line L1 (-73.875, -0.1) -> (-73.875, 0.1)
  arc A2 (-73.875, 0.1) -> (-74.025, 0.25) centre (-74.025, 0.1) ccw
  line L2 (-74.025, 0.25) -> (-75.725, 0.25)
  arc A3 (-75.725, 0.25) -> (-75.875, 0.1) centre (-75.725, 0.1) ccw
  line L3 (-75.875, 0.1) -> (-75.875, -0.1)
  constraints: 8 end point, 8 point on circle, 4 centre point
extrude "Extrusion35" add sketch "Sketch_78" along normal blind 1.5
sketch "Sketch_79" plane through (0, 44.5, 0) normal (0, 1, 0) x (1, 0, 0)
  arc A0 (-75.875, -3.3) -> (-75.725, -3.45) centre (-75.725, -3.3) ccw
  line L0 (-75.725, -3.45) -> (-74.025, -3.45)
  arc A1 (-74.025, -3.45) -> (-73.875, -3.3) centre (-74.025, -3.3) ccw
  line L1 (-73.875, -3.3) -> (-73.875, -3.1)
  arc A2 (-73.875, -3.1) -> (-74.025, -2.95) centre (-74.025, -3.1) ccw
  line L2 (-74.025, -2.95) -> (-75.725, -2.95)
  arc A3 (-75.725, -2.95) -> (-75.875, -3.1) centre (-75.725, -3.1) ccw
  line L3 (-75.875, -3.1) -> (-75.875, -3.3)
  constraints: 8 end point, 8 point on circle, 4 centre point
extrude "Extrusion36" add sketch "Sketch_79" along normal blind 1.5
sketch "Sketch_82" plane through (0, 49.5, 0) normal (0, 1, 0) x (1, 0, 0)
  line L0 (-105.15, 20.375) -> (-105.15, 19.625)
  line L1 (-105.15, 19.625) -> (-104.65, 19.625)
  line L2 (-104.65, 19.625) -> (-104.65, 20.375)
  line L3 (-104.65, 20.375) -> (-105.15, 20.375)
  constraints: 8 end point
sketch "Sketch_83" plane through (0, 49.5, 0) normal (0, 1, 0) x (1, 0, 0)
  line L0 (-105.15, 18.375) -> (-105.15, 17.625)
  line L1 (-105.15, 17.625) -> (-104.65, 17.625)
  line L2 (-104.65, 17.625) -> (-104.65, 18.375)
  line L3 (-104.65, 18.375) -> (-105.15, 18.375)
  constraints: 8 end point
sketch "Sketch_84" plane through (0, 49.5, 0) normal (0, 1, 0) x (1, 0, 0)
  line L0 (-105.15, 16.375) -> (-105.15, 15.625)
  line L1 (-105.15, 15.625) -> (-104.65, 15.625)
  line L2 (-104.65, 15.625) -> (-104.65, 16.375)
  line L3 (-104.65, 16.375) -> (-105.15, 16.375)
  constraints: 8 end point
sketch "Sketch_85" plane through (0, 49.5, 0) normal (0, 1, 0) x (1, 0, 0)
  line L0 (-105.15, 14.375) -> (-105.15, 13.625)
  line L1 (-105.15, 13.625) -> (-104.65, 13.625)
  line L2 (-104.65, 13.625) -> (-104.65, 14.375)
  line L3 (-104.65, 14.375) -> (-105.15, 14.375)
  constraints: 8 end point
sketch "Sketch_86" plane through (0, 49.5, 0) normal (0, 1, 0) x (1, 0, 0)
  line L0 (-103.15, 19.375) -> (-103.15, 18.625)
  line L1 (-103.15, 18.625) -> (-102.65, 18.625)
  line L2 (-102.65, 18.625) -> (-102.65, 19.375)
  line L3 (-102.65, 19.375) -> (-103.15, 19.375)
  constraints: 8 end point
sketch "Sketch_87" plane through (0, 49.5, 0) normal (0, 1, 0) x (1, 0, 0)
  line L0 (-103.15, 17.375) -> (-103.15, 16.625)
  line L1 (-103.15, 16.625) -> (-102.65, 16.625)
  line L2 (-102.65, 16.625) -> (-102.65, 17.375)
  line L3 (-102.65, 17.375) -> (-103.15, 17.375)
  constraints: 8 end point
sketch "Sketch_88" plane through (0, 49.5, 0) normal (0, 1, 0) x (1, 0, 0)
  line L0 (-103.15, 15.375) -> (-103.15, 14.625)
  line L1 (-103.15, 14.625) -> (-102.65, 14.625)
  line L2 (-102.65, 14.625) -> (-102.65, 15.375)
  line L3 (-102.65, 15.375) -> (-103.15, 15.375)
  constraints: 8 end point
extrude "Extrusion37" cut sketch "Sketch_82" against normal blind 0.5
extrude "Extrusion38" cut sketch "Sketch_83" against normal blind 0.5
extrude "Extrusion39" cut sketch "Sketch_84" against normal blind 0.5
extrude "Extrusion40" cut sketch "Sketch_85" against normal blind 0.5
extrude "Extrusion41" cut sketch "Sketch_86" against normal blind 0.5
extrude "Extrusion42" cut sketch "Sketch_87" against normal blind 0.5
extrude "Extrusion43" cut sketch "Sketch_88" against normal blind 0.5
sketch "Sketch_41" plane through (0, 44.5, 0) normal (0, 1, 0) x (1, 0, 0)
  line L0 (-79.125, 0.5) -> (-79.125, -0.5)
  line L1 (-79.125, -0.5) -> (-77.775, -0.5)
  arc A0 (-77.775, -0.5) -> (-77.575, -0.3) centre (-77.775, -0.3) ccw
  line L2 (-77.575, -0.3) -> (-77.575, 0.3)
  arc A1 (-77.575, 0.3) -> (-77.775, 0.5) centre (-77.775, 0.3) ccw
  line L3 (-77.775, 0.5) -> (-79.125, 0.5)
  constraints: 8 end point, 4 point on circle, 2 centre point
extrude "Extrusion44" add sketch "Sketch_41" along normal blind 3.5
sketch "Sketch_89" plane through (0, 44.5, 0) normal (0, 1, 0) x (1, 0, 0)
  arc A0 (-73.225, 2.9) -> (-73.025, 2.7) centre (-73.025, 2.9) ccw
  line L0 (-73.025, 2.7) -> (-71.675, 2.7)
  line L1 (-71.675, 2.7) -> (-71.675, 3.7)
  line L2 (-71.675, 3.7) -> (-73.025, 3.7)
  arc A1 (-73.025, 3.7) -> (-73.225, 3.5) centre (-73.025, 3.5) ccw
  line L3 (-73.225, 3.5) -> (-73.225, 2.9)
  constraints: 8 end point, 4 point on circle, 2 centre point
extrude "Extrusion45" add sketch "Sketch_89" along normal blind 3.5
sketch "Sketch_90" plane through (0, 44.5, 0) normal (0, 1, 0) x (1, 0, 0)
  arc A0 (-73.225, -3.5) -> (-73.025, -3.7) centre (-73.025, -3.5) ccw
  line L0 (-73.025, -3.7) -> (-71.675, -3.7)
  line L1 (-71.675, -3.7) -> (-71.675, -2.7)
  line L2 (-71.675, -2.7) -> (-73.025, -2.7)
  arc A1 (-73.025, -2.7) -> (-73.225, -2.9) centre (-73.025, -2.9) ccw
  line L3 (-73.225, -2.9) -> (-73.225, -3.5)
  constraints: 8 end point, 4 point on circle, 2 centre point
extrude "Extrusion46" add sketch "Sketch_90" along normal blind 3.5
sketch "Sketch_91" plane through (0, 0, 0) normal (0, 0, 1) x (1, 0, 0)
  line L0 (-97.7, 49.5) -> (-94.7, 44.5)
  line L1 (-94.7, 44.5) -> (-94.7, 49.5)
  line L2 (-94.7, 49.5) -> (-97.7, 49.5)
  constraints: 6 end point
extrude "Extrusion47" cut sketch "Sketch_91" against normal blind 50
sketch "Sketch_92" plane through (0, 43.5, 0) normal (0, 1, 0) x (1, 0, 0)
  line L0 (-110.2, 37.5) -> (-110.2, 27.5)
  line L1 (-110.2, 27.5) -> (-97.2, 27.5)
  arc A0 (-95.2, 25.5) -> (-97.2, 27.5) centre (-97.2, 25.5) ccw
  line L2 (-95.2, 25.5) -> (-94.7, 25.5)
  line L3 (-94.7, 25.5) -> (-94.7, 37.5)
  line L4 (-94.7, 37.5) -> (-110.2, 37.5)
  constraints: 10 end point, 2 point on circle, 1 centre point
extrude "Extrusion48" cut sketch "Sketch_92" against normal blind 12.5
ref_plane "K_XY" through (32, 6, 0) normal (0, 1, 0) x (1, 0, 0)
ref_plane "K_YZ" through (32, 6, 0) normal (1, 0, 0) x (0, 0, -1)
ref_plane "K_ZX" through (32, 6, 0) normal (0, 0, -1) x (0, 1, 0)
ref_plane "motor_XY" through (-3, 0, 0) normal (-1, 0, 0) x (0, 0, -1)
ref_plane "motor_YZ" through (-3, 0, 0) normal (0, 0, -1) x (0, -1, 0)
ref_plane "motor_ZX" through (-3, 0, 0) normal (0, -1, 0) x (-1, 0, 0)
body "Solid1"
